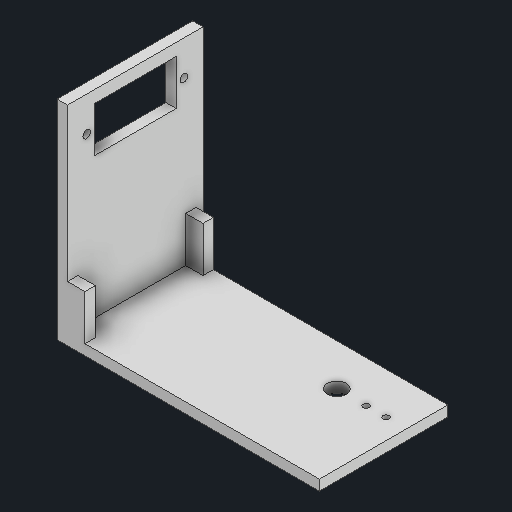
# Autodesk Inventor part: 03_Brazo_yaw
Saved by Autodesk Inventor 2027.2 (Build 312334000, 334)
## iProperties
Created: 2026-11-14
Part Number: 03_Brazo_yaw
Material: Genérico
Document SubType Name: Modeling
Designer: alexa
Density: 1 g/cm^3
Appearance: Valor por defecto
Mass: 14.4316 g
Surface Area: 109.963 cm^2
Volume: 14.4316 cm^3
Author: alexa
Autodesk Inventor part; units mm, degrees
ref_plane "Placa_horn_yaw_perfil_plano" through (0, 0, -12) normal (0, 0, 1) x (1, 0, 0)
sketch "Placa_horn_yaw_perfil" plane through (0, 0, -12) normal (0, 0, 1) x (1, 0, 0)
  line L0 (-55.5, -50) -> (20, -50)
  line L1 (20, -50) -> (20, -47)
  line L2 (20, -47) -> (-55.5, -47)
  line L3 (-55.5, -47) -> (-55.5, -50)
  constraints: 8 end point, 2 parallel, 1 horizontal, 1 perpendicular
extrude "Placa_horn_yaw" add sketch "Placa_horn_yaw_perfil" along normal blind 37
ref_plane "Soporte_servo_pitch_perfil_plano" through (0, 0, -14) normal (0, 0, 1) x (1, 0, 0)
sketch "Soporte_servo_pitch_perfil" plane through (0, 0, -14) normal (0, 0, 1) x (1, 0, 0)
  line L0 (-55.5, -50) -> (-52.5, -50)
  line L1 (-52.5, -50) -> (-52.5, 10)
  line L2 (-52.5, 10) -> (-55.5, 10)
  line L3 (-55.5, 10) -> (-55.5, -50)
  constraints: 8 end point, 2 parallel, 1 horizontal, 1 perpendicular
extrude "Soporte_servo_pitch" add sketch "Soporte_servo_pitch_perfil" along normal blind 39
ref_plane "Paso_cuerpo_MG90S_perfil_plano" through (-55.6, 0, 0) normal (1, 0, 0) x (0, 1, 0)
sketch "Paso_cuerpo_MG90S_perfil" plane through (-55.6, 0, 0) normal (1, 0, 0) x (0, 1, 0)
  line L0 (-6.5, -6.3) -> (6.5, -6.3)
  line L1 (6.5, -6.3) -> (6.5, 17.2)
  line L2 (6.5, 17.2) -> (-6.5, 17.2)
  line L3 (-6.5, 17.2) -> (-6.5, -6.3)
  constraints: 8 end point, 2 parallel, 1 horizontal, 1 perpendicular
extrude "Paso_cuerpo_MG90S" cut sketch "Paso_cuerpo_MG90S_perfil" along normal blind 3.2
ref_plane "Fijacion_servo_-8.5_perfil_plano" through (-55.7, 0, 0) normal (1, 0, 0) x (0, 1, 0)
sketch "Fijacion_servo_-8.5_perfil" plane through (-55.7, 0, 0) normal (1, 0, 0) x (0, 1, 0)
  circle A0 centre (0, -8.5) radius 1.1
  constraints: 1 centre point
extrude "Fijacion_servo_-8.5" cut sketch "Fijacion_servo_-8.5_perfil" along normal blind 3.4
ref_plane "Fijacion_servo_19.5_perfil_plano" through (-55.7, 0, 0) normal (1, 0, 0) x (0, 1, 0)
sketch "Fijacion_servo_19.5_perfil" plane through (-55.7, 0, 0) normal (1, 0, 0) x (0, 1, 0)
  circle A0 centre (0, 19.5) radius 1.1
  constraints: 1 centre point
extrude "Fijacion_servo_19.5" cut sketch "Fijacion_servo_19.5_perfil" along normal blind 3.4
ref_plane "Acceso_tornillo_central_horn_perfil_plano" through (0, -50.1, 0) normal (0, 1, 0) x (-1, 0, 0)
sketch "Acceso_tornillo_central_horn_perfil" plane through (0, -50.1, 0) normal (0, 1, 0) x (-1, 0, 0)
  circle A0 centre (0, 0) radius 2.75
  constraints: 1 centre point
extrude "Acceso_tornillo_central_horn" cut sketch "Acceso_tornillo_central_horn_perfil" along normal blind 3.2
ref_plane "Paso_horn_r_8.5_perfil_plano" through (0, -50.1, 0) normal (0, 1, 0) x (-1, 0, 0)
sketch "Paso_horn_r_8.5_perfil" plane through (0, -50.1, 0) normal (0, 1, 0) x (-1, 0, 0)
  circle A0 centre (-8.5, 0) radius 0.9
  constraints: 1 centre point
extrude "Paso_horn_r_8.5" cut sketch "Paso_horn_r_8.5_perfil" along normal blind 3.2
ref_plane "Paso_horn_r_14.2_perfil_plano" through (0, -50.1, 0) normal (0, 1, 0) x (-1, 0, 0)
sketch "Paso_horn_r_14.2_perfil" plane through (0, -50.1, 0) normal (0, 1, 0) x (-1, 0, 0)
  circle A0 centre (-14.2, 0) radius 0.9
  constraints: 1 centre point
extrude "Paso_horn_r_14.2" cut sketch "Paso_horn_r_14.2_perfil" along normal blind 3.2
ref_plane "Nervio_frontal_perfil_plano" through (0, 0, -12) normal (0, 0, 1) x (1, 0, 0)
sketch "Nervio_frontal_perfil" plane through (0, 0, -12) normal (0, 0, 1) x (1, 0, 0)
  line L0 (-52.5, -47) -> (-47.5, -47)
  line L1 (-47.5, -47) -> (-47.5, -34)
  line L2 (-47.5, -34) -> (-52.5, -34)
  line L3 (-52.5, -34) -> (-52.5, -47)
  constraints: 8 end point, 2 parallel, 1 horizontal, 1 perpendicular
extrude "Nervio_frontal" add sketch "Nervio_frontal_perfil" along normal blind 3
ref_plane "Nervio_posterior_perfil_plano" through (0, 0, 22) normal (0, 0, 1) x (1, 0, 0)
sketch "Nervio_posterior_perfil" plane through (0, 0, 22) normal (0, 0, 1) x (1, 0, 0)
  line L0 (-52.5, -47) -> (-47.5, -47)
  line L1 (-47.5, -47) -> (-47.5, -34)
  line L2 (-47.5, -34) -> (-52.5, -34)
  line L3 (-52.5, -34) -> (-52.5, -47)
  constraints: 8 end point, 2 parallel, 1 horizontal, 1 perpendicular
extrude "Nervio_posterior" add sketch "Nervio_posterior_perfil" along normal blind 3
ref_plane "Yaw_apoyo" through (0, -50, 0) normal (0, 1, 0) x (-1, 0, 0)
ref_plane "Pitch_apoyo" through (-38, 0, 0) normal (1, 0, 0) x (0, 1, 0)
ref_plane "Servo_pitch_ref_1" through (-52.5, 0, 0) normal (0, 0, -1) x (1, 0, 0)
ref_plane "Servo_pitch_ref_2" through (-52.5, 0, 0) normal (0, 1, 0) x (1, 0, 0)
ref_plane "Servo_pitch_ref_3" through (-52.5, 0, 0) normal (1, 0, 0) x (0, 1, 0)
ref_plane "Horn_yaw_ref_1" through (0, -50, 0) normal (0, -1, 0) x (1, 0, 0)
ref_plane "Horn_yaw_ref_2" through (0, -50, 0) normal (1, 0, 0) x (0, 1, 0)
ref_plane "Horn_yaw_ref_3" through (0, -50, 0) normal (0, 0, 1) x (1, 0, 0)
